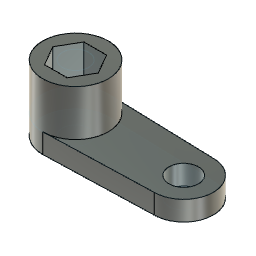
encloser_support_2024-09-24 (Autodesk Fusion 360 design; units mm, degrees)
Autodesk Fusion 360 part; units mm, degrees
sketch "스케치1" plane through (0, 0, 0) normal (0, 0, 1) x (1, 0, 0)
  circle A0 centre (16.5, 0) radius 2.25
  line L0 (0, 5) -> (16.5, 4.5)
  line L1 (0, -5) -> (16.5, -4.5)
  arc A1 (0.3027, 4.9908) -> (0.3027, -4.9908) centre (0, 0) ccw
  arc A2 (16.5, -4.5) -> (16.5, 4.5) centre (16.5, 0) ccw
  dimension "d3" = 10
  dimension "d4" = 4.5
  dimension "d5" = 9
  constraint coincident A1.centre origin
  constraint concentric A0 A2
  constraint coincident L0.start A1
  constraint coincident L1.start A1
  constraint coincident L1 A1.end
  constraint coincident L0 A1.start
  measures "d3" diameter of A1
  measures "d4" diameter of A0
  measures "d5" diameter of A2
extrude "돌출1" add sketch "스케치1" along normal blind 3
sketch "스케치2" plane through (0, 0, 3) normal (0, 0, 1) x (-1, 0, 0)
  circle A0 centre (-16.5, 0) radius 2.25
  arc A1 (0, -5) -> (0, 5) centre (0, 0) ccw
  line L0 (0, 5) -> (-16.5, 4.5)
  arc A2 (-16.5, 4.5) -> (-16.5, -4.5) centre (-16.5, 0) ccw
  line L1 (-16.5, -4.5) -> (0, -5)
sketch "스케치3" plane through (0, 0, 3) normal (0, 0, 1) x (-1, 0, 0)
  circle A0 centre (0, 0) radius 5
  constraint coincident A0.centre origin
extrude "돌출2" add sketch "스케치3" along normal blind 7
sketch "스케치4" plane through (0, 0, 0) normal (0, 0, -1) x (1, 0, 0)
  circle A0 centre (16.5, 0) radius 2.25
  arc A1 (0, 5) -> (0, -5) centre (0, 0) ccw
  line L0 (0, -5) -> (16.5, -4.5)
  arc A2 (16.5, -4.5) -> (16.5, 4.5) centre (16.5, 0) ccw
  line L1 (16.5, 4.5) -> (0, 5)
  circle A3 centre (0, 0) radius 2
  dimension "d10" = 4
  constraint coincident A1.centre A3.centre
  measures "d10" diameter of A3
extrude "돌출3" cut sketch "스케치4" against normal blind 10 contours A3
sketch "스케치5" plane through (0, 0, 0) normal (0, 0, -1) x (1, 0, 0)
  circle A0 centre (0, 0) radius 2
  circle A1 centre (16.5, 0) radius 2.25
  arc A2 (0, 5) -> (0, -5) centre (0, 0) ccw
  line L0 (0, -5) -> (16.5, -4.5)
  arc A3 (16.5, -4.5) -> (16.5, 4.5) centre (16.5, 0) ccw
  line L1 (16.5, 4.5) -> (0, 5)
sketch "스케치6" plane through (0, 0, 10) normal (0, 0, 1) x (-1, 0, 0)
  circle A0 centre (0, 0) radius 2
  circle A1 centre (0, 0) radius 5
sketch "스케치7" plane through (0, 0, 10) normal (0, 0, 1) x (-1, 0, 0)
  line L0 (1.7321, -3) -> (3.4641, 0)
  line L1 (3.4641, 0) -> (1.7321, 3)
  line L2 (1.7321, 3) -> (-1.7321, 3)
  line L3 (-1.7321, 3) -> (-3.4641, 0)
  line L4 (-3.4641, 0) -> (-1.7321, -3)
  line L5 (-1.7321, -3) -> (1.7321, -3)
extrude "돌출4" cut sketch "스케치7" against normal blind 7
